Autodesk Fusion 360 part; units mm, degrees
(part 5 of 8)
sketch "Adapter Washer 4 Outer" plane through (-21.2132, -21.2132, 0) normal (0.707107, 0.707107, 0) x (0, 0, 1) in component "REF M4 Adapter Fasteners"
  circle A0 centre (22.6274, -22.6274) radius 4.5
  circle A1 centre (22.6274, -22.6274) radius 2.15
  dimension "d1308" = 22.6274
  dimension "d1309" = 22.6274
  dimension "d1310" = 9
  dimension "d1311" = 4.3
  measures "d1308" horizontal distance of origin A0.centre
  measures "d1309" vertical distance of origin A0.centre
  measures "d1310" diameter of A0
  measures "d1311" diameter of A1
extrude "Adapter Washer 4" add sketch "Adapter Washer 4 Outer" along normal blind 1 separate body makes body 52 in component "REF M4 Adapter Fasteners"
ref_plane "WorkPlane16" through (-3.182, -3.182, 12.125) normal (0.707107, 0.707107, 0) x (0, 0, 1) in component "REF M4 Adapter Fasteners"
sketch "Adapter Nut Hex 4" plane through (-3.182, -3.182, 0) normal (0.707107, 0.707107, 0) x (0, 0, 1) in component "REF M4 Adapter Fasteners"
  circle A0 centre (22.6274, -22.6274) radius 4.0415 construction
  line L0 (26.6689, -22.6274) -> (24.6481, -19.1274)
  line L1 (24.6481, -19.1274) -> (20.6067, -19.1274)
  line L2 (20.6067, -19.1274) -> (18.586, -22.6274)
  line L3 (18.586, -22.6274) -> (20.6067, -26.1274)
  line L4 (20.6067, -26.1274) -> (24.6481, -26.1274)
  line L5 (24.6481, -26.1274) -> (26.6689, -22.6274)
  dimension "d1316" = 22.6274
  dimension "d1317" = 22.6274
  dimension "d1318" = 8.0829
  constraint coincident A0 L0.start
  constraint coincident A0 L0.end
  constraint coincident A0 L1.end
  constraint coincident A0 L2.end
  constraint coincident A0 L3.end
  constraint coincident A0 L4.end
  constraint equal L0 L1
  constraint equal L0 L2
  constraint equal L0 L3
  constraint equal L0 L4
  constraint equal L0 L5
  constraint horizontal L1
  measures "d1316" horizontal distance of origin A0.centre
  measures "d1317" vertical distance of origin A0.centre
  measures "d1318" diameter of A0
extrude "Adapter Nut 4" add sketch "Adapter Nut Hex 4" along normal blind 3.2 separate body makes body 53 in component "REF M4 Adapter Fasteners"
sketch "Nut Thread Clearance 4" plane through (-3.182, -3.182, 0) normal (0.707107, 0.707107, 0) x (0, 0, 1) in component "REF M4 Adapter Fasteners"
  circle A0 centre (22.6274, -22.6274) radius 2.15
  dimension "d1321" = 22.6274
  dimension "d1322" = 22.6274
  dimension "d1323" = 4.3
  measures "d1321" horizontal distance of origin A0.centre
  measures "d1322" vertical distance of origin A0.centre
  measures "d1323" diameter of A0
extrude "Nut Bore 4" cut sketch "Nut Thread Clearance 4" along normal blind 3.2 bodies 53 in component "REF M4 Adapter Fasteners"
ref_plane "WorkPlane1" through (0, 0, 12.125) normal (0.707107, 0.707107, 0) x (0, 0, 1) in component "REF M3 Support Fasteners"
sketch "M3 Pattern Axis" plane through (0, 0, 0) normal (0.707107, 0.707107, 0) x (0, 0, 1) in component "REF M3 Support Fasteners"
  circle A0 centre (0, 0) radius 0.5
  dimension "d1328" = 1
  measures "d1328" diameter of A0
ref_plane "WorkPlane2" through (-6.1518, -6.1518, 12.125) normal (0.707107, 0.707107, 0) x (0, 0, 1) in component "REF M3 Support Fasteners"
sketch "M3 Shank Profile" plane through (-6.1518, -6.1518, 0) normal (0.707107, 0.707107, 0) x (0, 0, 1) in component "REF M3 Support Fasteners"
  line L0 (0, 0) -> (17, 0) construction
  circle A0 centre (17, 0) radius 1.5
  dimension "d1331" = 17
  dimension "d1332" = 3
  constraint horizontal L0
  measures "d1331" distance of L0.start L0.end
  measures "d1332" diameter of A0
extrude "M3 Shank" add sketch "M3 Shank Profile" along normal blind 45 separate body makes body 54 in component "REF M3 Support Fasteners"
ref_plane "WorkPlane3" through (25.668, 25.668, 12.125) normal (0.707107, 0.707107, 0) x (0, 0, 1) in component "REF M3 Support Fasteners"
sketch "M3 Head Profile" plane through (25.668, 25.668, 0) normal (0.707107, 0.707107, 0) x (0, 0, 1) in component "REF M3 Support Fasteners"
  line L0 (0, 0) -> (17, 0) construction
  circle A0 centre (17, 0) radius 2.75
  dimension "d1337" = 17
  dimension "d1338" = 5.5
  constraint horizontal L0
  measures "d1337" distance of L0.start L0.end
  measures "d1338" diameter of A0
extrude "M3 Head" add sketch "M3 Head Profile" along normal blind 3 separate body makes body 55 in component "REF M3 Support Fasteners"
ref_plane "WorkPlane4" through (25.3144, 25.3144, 12.125) normal (0.707107, 0.707107, 0) x (0, 0, 1) in component "REF M3 Support Fasteners"
sketch "Rear M3 Washer Profile" plane through (25.3144, 25.3144, 0) normal (0.707107, 0.707107, 0) x (0, 0, 1) in component "REF M3 Support Fasteners"
  line L0 (0, 0) -> (17, 0) construction
  circle A0 centre (17, 0) radius 3.5
  circle A1 centre (17, 0) radius 1.65
  dimension "d1343" = 17
  dimension "d1344" = 7
  dimension "d1345" = 3.3
  constraint horizontal L0
  measures "d1343" distance of L0.start L0.end
  measures "d1344" diameter of A0
  measures "d1345" diameter of A1
extrude "Rear M3 Washer" add sketch "Rear M3 Washer Profile" along normal blind 0.5 separate body makes body 56 in component "REF M3 Support Fasteners"
ref_plane "WorkPlane5" through (-2.1213, -2.1213, 12.125) normal (0.707107, 0.707107, 0) x (0, 0, 1) in component "REF M3 Support Fasteners"
sketch "Front M3 Washer Profile" plane through (-2.1213, -2.1213, 0) normal (0.707107, 0.707107, 0) x (0, 0, 1) in component "REF M3 Support Fasteners"
  line L0 (0, 0) -> (17, 0) construction
  circle A0 centre (17, 0) radius 3.5
  circle A1 centre (17, 0) radius 1.65
  dimension "d1350" = 17
  dimension "d1351" = 7
  dimension "d1352" = 3.3
  constraint horizontal L0
  measures "d1350" distance of L0.start L0.end
  measures "d1351" diameter of A0
  measures "d1352" diameter of A1
extrude "Front M3 Washer" add sketch "Front M3 Washer Profile" along normal blind 0.5 separate body makes body 57 in component "REF M3 Support Fasteners"
ref_plane "WorkPlane6" through (-4.9497, -4.9497, 12.125) normal (0.707107, 0.707107, 0) x (0, 0, 1) in component "REF M3 Support Fasteners"
sketch "Front M3 Nyloc Envelope Profile" plane through (-4.9497, -4.9497, 0) normal (0.707107, 0.707107, 0) x (0, 0, 1) in component "REF M3 Support Fasteners"
  line L0 (0, 0) -> (17, 0) construction
  circle A0 centre (17, 0) radius 3.18
  circle A1 centre (17, 0) radius 1.65
  dimension "d1357" = 17
  dimension "d1358" = 6.36
  dimension "d1359" = 3.3
  constraint horizontal L0
  measures "d1357" distance of L0.start L0.end
  measures "d1358" diameter of A0
  measures "d1359" diameter of A1
extrude "Front M3 Nyloc Envelope" add sketch "Front M3 Nyloc Envelope Profile" along normal blind 4 separate body makes body 58 in component "REF M3 Support Fasteners"
pattern_circular "Three M3 Support Sets" count 3 over 360 about axis through (0, 0, 0) along (0.707107, 0.707107, 0) of "M3 Shank", "M3 Head", "Rear M3 Washer", "Front M3 Washer", "Front M3 Nyloc Envelope" makes body 59 at (26.4156, 3.7072, -9.1843) makes body 60 at (38.5579, 14.1923, -9.631) makes body 61 at (37.5691, 13.0597, -9.7105) makes body 62 at (10.487, -14.0225, -9.7105) makes body 63 at (8.453, -16.4669, -9.8079) makes body 64 at (5.063, 25.0597, -7.1178) makes body 65 at (15.0384, 39.126, -9.992) makes body 66 at (13.2406, 37.3882, -10.1537) makes body 67 at (-13.8416, 10.306, -10.1537) makes body 68 at (-16.243, 8.2291, -10.3563) in component "REF M3 Support Fasteners"
component "A Housing" placed x (1, 0, 0) y (0, 1, 0) z (0, 0, 1) at (0, 0, 0)
component "B Moving Body" placed x (1, 0, 0) y (0, 1, 0) z (0, 0, 1) at (0, 0, 0)
component "D Rear Bearing Holder" placed x (1, 0, 0) y (0, 1, 0) z (0, 0, 1) at (0, 0, 0)
component "C Front Bearing Cap" placed x (1, 0, 0) y (0, 1, 0) z (0, 0, 1) at (0, 0, 0)
component "E Rear Bearing Cap" placed x (1, 0, 0) y (0, 1, 0) z (0, 0, 1) at (0, 0, 0)
component "F Metal Hub Adapter" placed x (1, 0, 0) y (0, 1, 0) z (0, 0, 1) at (0, 0, 0)
component "REF Two 608 Bearings" placed x (1, 0, 0) y (0, 1, 0) z (0, 0, 1) at (0, 0, 0)
component "REF Steel Shaft 8 x 60" placed x (1, 0, 0) y (0, 1, 0) z (0, 0, 1) at (0, 0, 0)
component "REF Inner Ring Spacers" placed x (1, 0, 0) y (0, 1, 0) z (0, 0, 1) at (0, 0, 0)
component "REF Split Collar Envelopes" placed x (1, 0, 0) y (0, 1, 0) z (0, 0, 1) at (0, 0, 0)
component "REF Metal Support Spacers" placed x (1, 0, 0) y (0, 1, 0) z (0, 0, 1) at (0, 0, 0)
component "REF Hub Compression Sleeves" placed x (1, 0, 0) y (0, 1, 0) z (0, 0, 1) at (0, 0, 0)
component "REF Sonic Hub Envelope" placed x (1, 0, 0) y (0, 1, 0) z (0, 0, 1) at (0, 0, 0)
component "REF M4 Hub Screws" placed x (1, 0, 0) y (0, 1, 0) z (0, 0, 1) at (0, 0, 0)
component "REF M4 Adapter Fasteners" placed x (1, 0, 0) y (0, 1, 0) z (0, 0, 1) at (0, 0, 0)
component "REF M3 Support Fasteners" placed x (1, 0, 0) y (0, 1, 0) z (0, 0, 1) at (0, 0, 0)
equation "bodyWidth = 150 mm" comment "Regular octagon across flats; corner diameter is larger."
equation "bodyLength = 260 mm" comment "Overall straight length of the shared master blank."
equation "splitAngle = 45 deg" comment "Keep this lesson angle at45 degrees."
equation "faceGap = 1 mm" comment "Gap between the two printed joint faces."
equation "wall = 4.5 mm" comment "Integrated shell and side brace radial thickness."
equation "faceHalfWidth = bodyWidth * ( sqrt(2) - 1 ) / 2" comment "Half-width of each outer planar facet."
equation "memberWidth = 8 mm" comment "Nominal brace and corner chord width in a facet."
equation "nodeHalfWidth = faceHalfWidth - memberWidth / 2" comment "Chord centerlines measured from facet center."
equation "jointNodeQ = 7 mm" comment "First truss skeleton row from the center joint plane."
equation "endRim = 10 mm" comment "Uncut axial rim at each distant end."
equation "endNodeX = bodyLength / 2 - endRim + memberWidth / 2" comment "Last skeleton row before aperture inset."
equation "apertureRadius = 1.5 mm" comment "Rounded internal corners at triangular openings."
equation "spokeWidth = 10 mm" comment "Width of each deep bearing bulkhead spoke."
equation "spokeDepth = 18 mm" comment "Bulkhead depth normal to the diagonal joint face."
equation "carrierOD = 52 mm" comment "Outside of integrated A front bearing carrier."
equation "rearCarrierClearance = 46 mm" comment "Internal carrier relief above front bearing shoulder."
equation "tubeCornerChamfer = 0.5 mm" comment "Exposed outside octagon corner bevel."
equation "tubeRimChamfer = 0.3 mm" comment "End rim and print-contact edge relief."
equation "cordStation = bodyLength / 2 - endRim / 2" comment "Load-test cord port center measured along body X."
equation "bearingOD = 22 mm" comment "608 measured outside diameter."
equation "bearingID = 8 mm" comment "608 bore."
equation "bearingWidth = 7 mm" comment "608 width."
equation "seatAllowance = 0.2 mm" comment "Trial DIAMETRAL clearance; choose with printed coupon."
equation "seatDiameter = bearingOD + seatAllowance" comment "Measured fit controls this."
equation "coreOD = 44 mm" comment "Bearing holder outer diameter."
equation "raceRelief = 19.5 mm" comment "Outer-ring shoulder opening; verify seals."
equation "frontSeatDepth = 7.1 mm" comment "0.1 mm outer-ring axial allowance."
equation "rearSeatDepth = 7.2 mm" comment "0.2 mm outer-ring axial float."
equation "shoulder = 3 mm" comment "Backing behind each bearing seat."
equation "supportSpacer = 12 mm" comment "Purchased metal M3 spacer length."
equation "supportCircle = 34 mm" comment "Three M3 support bolts."
equation "supportSpacerOD = 6 mm" comment "Purchased spacer outside diameter."
equation "capThickness = 3 mm" comment "Both printed outer-ring retaining caps."
equation "m3Clearance = 3.3 mm" comment "M3 through holes."
equation "m4Clearance = 4.3 mm" comment "M4 through holes."
equation "qFront = faceGap / 2" comment "Front bearing starts at A mating face."
equation "qFrontBack = qFront + frontSeatDepth + shoulder" comment "End of integrated A holder."
equation "qRearBase = qFrontBack + supportSpacer" comment "Start of removable rear holder."
equation "qRearBearing = qRearBase + shoulder" comment "Rear bearing inner end."
equation "qRearEnd = qRearBearing + rearSeatDepth" comment "Rear holder outer end."
equation "bearingSpacing = qRearBearing - qFront" comment "Derived support-center spacing, not a bearing rating."
equation "mountOD = 76 mm" comment "B mount and F flange outside diameter."
equation "mountCircle = 64 mm" comment "Four M4 attachment holes."
equation "mountOpening = 50.3 mm" comment "B through opening."
equation "hubFace = -23 mm" comment "Metal hub flat mounting face."
equation "adapterThickness = 6 mm" comment "F flange and metal compression sleeve length."
equation "pilotDiameter = 50 mm" comment "F shallow centering pilot."
equation "pilotInside = 34 mm" comment "Clearance around metal hub."
equation "pilotHeight = 2 mm" comment "Short pilot only."
equation "hubHoleSpacing = 16 mm" comment "Metal Sonic hub square hole spacing."
equation "sleeveOD = 8 mm" comment "M4 metal compression sleeves."
equation "sleeveAllowance = 0.2 mm" comment "Trial DIAMETRAL sleeve clearance."
equation "shaftClearance = 8.5 mm" comment "F clearance hole; not a bearing."
equation "nutAF = 7.2 mm" comment "M4 nominal 7 AF nut trial pocket."
equation "nutDepth = 4 mm" comment "Open front M4 nut pocket."
equation "rootRadius = 1 mm" comment "Hub-to-wall blend."
equation "entryChamfer = 0.4 mm" comment "Assembly lead-in."
equation "bedRelief = 0.3 mm" comment "Bed-contact edge allowance."
equation "d59 = bodyWidth"
equation "d60 = bodyLength"
equation "d62 = splitAngle"
equation "d64 = -faceGap / 2"
equation "d65 = -faceGap / 2"
equation "d66 = wall"
equation "d67 = wall"
equation "d70 = bodyWidth / 2"
equation "d72 = abs(( 1 ) * ( ( ( 1 ) * jointNodeQ * sqrt(2) - bodyWidth / 2 * cos(0 deg) + ( ( -1 ) * nodeHalfWidth ) * sin(0 deg) ) + ( 0 ) * ( ( 1 ) * endNodeX - ( ( 1 ) * jointNodeQ * sqrt(2) - bodyWidth / 2 * cos(0 deg) + ( ( -1 ) * nodeHalfWidth ) * sin(0 deg) ) ) ) + ( 0 ) * ( ( -1 ) * nodeHalfWidth ))"
equation "d73 = abs(( 0 ) * ( ( ( 1 ) * jointNodeQ * sqrt(2) - bodyWidth / 2 * cos(0 deg) + ( ( -1 ) * nodeHalfWidth ) * sin(0 deg) ) + ( 0 ) * ( ( 1 ) * endNodeX - ( ( 1 ) * jointNodeQ * sqrt(2) - bodyWidth / 2 * cos(0 deg) + ( ( -1 ) * nodeHalfWidth ) * sin(0 deg) ) ) ) + ( -1 ) * ( ( -1 ) * nodeHalfWidth ))"
equation "d74 = abs(( 1 ) * ( ( ( 1 ) * jointNodeQ * sqrt(2) - bodyWidth / 2 * cos(0 deg) + ( ( 1 ) * nodeHalfWidth ) * sin(0 deg) ) + ( 0 ) * ( ( 1 ) * endNodeX - ( ( 1 ) * jointNodeQ * sqrt(2) - bodyWidth / 2 * cos(0 deg) + ( ( 1 ) * nodeHalfWidth ) * sin(0 deg) ) ) ) + ( 0 ) * ( ( 1 ) * nodeHalfWidth ))"
equation "d75 = abs(( 0 ) * ( ( ( 1 ) * jointNodeQ * sqrt(2) - bodyWidth / 2 * cos(0 deg) + ( ( 1 ) * nodeHalfWidth ) * sin(0 deg) ) + ( 0 ) * ( ( 1 ) * endNodeX - ( ( 1 ) * jointNodeQ * sqrt(2) - bodyWidth / 2 * cos(0 deg) + ( ( 1 ) * nodeHalfWidth ) * sin(0 deg) ) ) ) + ( -1 ) * ( ( 1 ) * nodeHalfWidth ))"
equation "d76 = abs(( 1 ) * ( ( ( 1 ) * jointNodeQ * sqrt(2) - bodyWidth / 2 * cos(0 deg) + ( ( -1 ) * nodeHalfWidth ) * sin(0 deg) ) + ( 0.666666666666667 ) * ( ( 1 ) * endNodeX - ( ( 1 ) * jointNodeQ * sqrt(2) - bodyWidth / 2 * cos(0 deg) + ( ( -1 ) * nodeHalfWidth ) * sin(0 deg) ) ) ) + ( 0 ) * ( ( -1 ) * nodeHalfWidth ))"
equation "d77 = abs(( 0 ) * ( ( ( 1 ) * jointNodeQ * sqrt(2) - bodyWidth / 2 * cos(0 deg) + ( ( -1 ) * nodeHalfWidth ) * sin(0 deg) ) + ( 0.666666666666667 ) * ( ( 1 ) * endNodeX - ( ( 1 ) * jointNodeQ * sqrt(2) - bodyWidth / 2 * cos(0 deg) + ( ( -1 ) * nodeHalfWidth ) * sin(0 deg) ) ) ) + ( -1 ) * ( ( -1 ) * nodeHalfWidth ))"
equation "d78 = -memberWidth / 2"
equation "d79 = -( wall + 0.2 mm )"
equation "d81 = abs(( 1 ) * ( ( ( 1 ) * jointNodeQ * sqrt(2) - bodyWidth / 2 * cos(0 deg) + ( ( 1 ) * nodeHalfWidth ) * sin(0 deg) ) + ( 0 ) * ( ( 1 ) * endNodeX - ( ( 1 ) * jointNodeQ * sqrt(2) - bodyWidth / 2 * cos(0 deg) + ( ( 1 ) * nodeHalfWidth ) * sin(0 deg) ) ) ) + ( 0 ) * ( ( 1 ) * nodeHalfWidth ))"
equation "d82 = abs(( 0 ) * ( ( ( 1 ) * jointNodeQ * sqrt(2) - bodyWidth / 2 * cos(0 deg) + ( ( 1 ) * nodeHalfWidth ) * sin(0 deg) ) + ( 0 ) * ( ( 1 ) * endNodeX - ( ( 1 ) * jointNodeQ * sqrt(2) - bodyWidth / 2 * cos(0 deg) + ( ( 1 ) * nodeHalfWidth ) * sin(0 deg) ) ) ) + ( -1 ) * ( ( 1 ) * nodeHalfWidth ))"
equation "d83 = abs(( 1 ) * ( ( ( 1 ) * jointNodeQ * sqrt(2) - bodyWidth / 2 * cos(0 deg) + ( ( -1 ) * nodeHalfWidth ) * sin(0 deg) ) + ( 0.666666666666667 ) * ( ( 1 ) * endNodeX - ( ( 1 ) * jointNodeQ * sqrt(2) - bodyWidth / 2 * cos(0 deg) + ( ( -1 ) * nodeHalfWidth ) * sin(0 deg) ) ) ) + ( 0 ) * ( ( -1 ) * nodeHalfWidth ))"
equation "d84 = abs(( 0 ) * ( ( ( 1 ) * jointNodeQ * sqrt(2) - bodyWidth / 2 * cos(0 deg) + ( ( -1 ) * nodeHalfWidth ) * sin(0 deg) ) + ( 0.666666666666667 ) * ( ( 1 ) * endNodeX - ( ( 1 ) * jointNodeQ * sqrt(2) - bodyWidth / 2 * cos(0 deg) + ( ( -1 ) * nodeHalfWidth ) * sin(0 deg) ) ) ) + ( -1 ) * ( ( -1 ) * nodeHalfWidth ))"
equation "d85 = abs(( 1 ) * ( ( ( 1 ) * jointNodeQ * sqrt(2) - bodyWidth / 2 * cos(0 deg) + ( ( 1 ) * nodeHalfWidth ) * sin(0 deg) ) + ( 0.833333333333333 ) * ( ( 1 ) * endNodeX - ( ( 1 ) * jointNodeQ * sqrt(2) - bodyWidth / 2 * cos(0 deg) + ( ( 1 ) * nodeHalfWidth ) * sin(0 deg) ) ) ) + ( 0 ) * ( ( 1 ) * nodeHalfWidth ))"
equation "d86 = abs(( 0 ) * ( ( ( 1 ) * jointNodeQ * sqrt(2) - bodyWidth / 2 * cos(0 deg) + ( ( 1 ) * nodeHalfWidth ) * sin(0 deg) ) + ( 0.833333333333333 ) * ( ( 1 ) * endNodeX - ( ( 1 ) * jointNodeQ * sqrt(2) - bodyWidth / 2 * cos(0 deg) + ( ( 1 ) * nodeHalfWidth ) * sin(0 deg) ) ) ) + ( -1 ) * ( ( 1 ) * nodeHalfWidth ))"
equation "d87 = memberWidth / 2"
equation "d88 = -( wall + 0.2 mm )"
equation "d90 = abs(( 1 ) * ( ( ( 1 ) * jointNodeQ * sqrt(2) - bodyWidth / 2 * cos(0 deg) + ( ( -1 ) * nodeHalfWidth ) * sin(0 deg) ) + ( 0.666666666666667 ) * ( ( 1 ) * endNodeX - ( ( 1 ) * jointNodeQ * sqrt(2) - bodyWidth / 2 * cos(0 deg) + ( ( -1 ) * nodeHalfWidth ) * sin(0 deg) ) ) ) + ( 0 ) * ( ( -1 ) * nodeHalfWidth ))"
equation "d91 = abs(( 0 ) * ( ( ( 1 ) * jointNodeQ * sqrt(2) - bodyWidth / 2 * cos(0 deg) + ( ( -1 ) * nodeHalfWidth ) * sin(0 deg) ) + ( 0.666666666666667 ) * ( ( 1 ) * endNodeX - ( ( 1 ) * jointNodeQ * sqrt(2) - bodyWidth / 2 * cos(0 deg) + ( ( -1 ) * nodeHalfWidth ) * sin(0 deg) ) ) ) + ( -1 ) * ( ( -1 ) * nodeHalfWidth ))"
equation "d92 = abs(( 1 ) * ( ( ( 1 ) * jointNodeQ * sqrt(2) - bodyWidth / 2 * cos(0 deg) + ( ( 1 ) * nodeHalfWidth ) * sin(0 deg) ) + ( 0.833333333333333 ) * ( ( 1 ) * endNodeX - ( ( 1 ) * jointNodeQ * sqrt(2) - bodyWidth / 2 * cos(0 deg) + ( ( 1 ) * nodeHalfWidth ) * sin(0 deg) ) ) ) + ( 0 ) * ( ( 1 ) * nodeHalfWidth ))"
equation "d93 = abs(( 0 ) * ( ( ( 1 ) * jointNodeQ * sqrt(2) - bodyWidth / 2 * cos(0 deg) + ( ( 1 ) * nodeHalfWidth ) * sin(0 deg) ) + ( 0.833333333333333 ) * ( ( 1 ) * endNodeX - ( ( 1 ) * jointNodeQ * sqrt(2) - bodyWidth / 2 * cos(0 deg) + ( ( 1 ) * nodeHalfWidth ) * sin(0 deg) ) ) ) + ( -1 ) * ( ( 1 ) * nodeHalfWidth ))"
equation "d94 = abs(( 1 ) * ( ( ( 1 ) * jointNodeQ * sqrt(2) - bodyWidth / 2 * cos(0 deg) + ( ( -1 ) * nodeHalfWidth ) * sin(0 deg) ) + ( 1 ) * ( ( 1 ) * endNodeX - ( ( 1 ) * jointNodeQ * sqrt(2) - bodyWidth / 2 * cos(0 deg) + ( ( -1 ) * nodeHalfWidth ) * sin(0 deg) ) ) ) + ( 0 ) * ( ( -1 ) * nodeHalfWidth ))"
equation "d95 = abs(( 0 ) * ( ( ( 1 ) * jointNodeQ * sqrt(2) - bodyWidth / 2 * cos(0 deg) + ( ( -1 ) * nodeHalfWidth ) * sin(0 deg) ) + ( 1 ) * ( ( 1 ) * endNodeX - ( ( 1 ) * jointNodeQ * sqrt(2) - bodyWidth / 2 * cos(0 deg) + ( ( -1 ) * nodeHalfWidth ) * sin(0 deg) ) ) ) + ( -1 ) * ( ( -1 ) * nodeHalfWidth ))"
equation "d96 = -memberWidth / 2"
equation "d97 = -( wall + 0.2 mm )"
equation "d99 = abs(( 1 ) * ( ( ( 1 ) * jointNodeQ * sqrt(2) - bodyWidth / 2 * cos(0 deg) + ( ( 1 ) * nodeHalfWidth ) * sin(0 deg) ) + ( 0.833333333333333 ) * ( ( 1 ) * endNodeX - ( ( 1 ) * jointNodeQ * sqrt(2) - bodyWidth / 2 * cos(0 deg) + ( ( 1 ) * nodeHalfWidth ) * sin(0 deg) ) ) ) + ( 0 ) * ( ( 1 ) * nodeHalfWidth ))"
equation "d100 = abs(( 0 ) * ( ( ( 1 ) * jointNodeQ * sqrt(2) - bodyWidth / 2 * cos(0 deg) + ( ( 1 ) * nodeHalfWidth ) * sin(0 deg) ) + ( 0.833333333333333 ) * ( ( 1 ) * endNodeX - ( ( 1 ) * jointNodeQ * sqrt(2) - bodyWidth / 2 * cos(0 deg) + ( ( 1 ) * nodeHalfWidth ) * sin(0 deg) ) ) ) + ( -1 ) * ( ( 1 ) * nodeHalfWidth ))"
equation "d101 = abs(( 1 ) * ( ( ( 1 ) * jointNodeQ * sqrt(2) - bodyWidth / 2 * cos(0 deg) + ( ( -1 ) * nodeHalfWidth ) * sin(0 deg) ) + ( 1 ) * ( ( 1 ) * endNodeX - ( ( 1 ) * jointNodeQ * sqrt(2) - bodyWidth / 2 * cos(0 deg) + ( ( -1 ) * nodeHalfWidth ) * sin(0 deg) ) ) ) + ( 0 ) * ( ( -1 ) * nodeHalfWidth ))"
equation "d102 = abs(( 0 ) * ( ( ( 1 ) * jointNodeQ * sqrt(2) - bodyWidth / 2 * cos(0 deg) + ( ( -1 ) * nodeHalfWidth ) * sin(0 deg) ) + ( 1 ) * ( ( 1 ) * endNodeX - ( ( 1 ) * jointNodeQ * sqrt(2) - bodyWidth / 2 * cos(0 deg) + ( ( -1 ) * nodeHalfWidth ) * sin(0 deg) ) ) ) + ( -1 ) * ( ( -1 ) * nodeHalfWidth ))"
equation "d103 = abs(( 1 ) * ( ( ( 1 ) * jointNodeQ * sqrt(2) - bodyWidth / 2 * cos(0 deg) + ( ( 1 ) * nodeHalfWidth ) * sin(0 deg) ) + ( 1 ) * ( ( 1 ) * endNodeX - ( ( 1 ) * jointNodeQ * sqrt(2) - bodyWidth / 2 * cos(0 deg) + ( ( 1 ) * nodeHalfWidth ) * sin(0 deg) ) ) ) + ( 0 ) * ( ( 1 ) * nodeHalfWidth ))"
equation "d104 = abs(( 0 ) * ( ( ( 1 ) * jointNodeQ * sqrt(2) - bodyWidth / 2 * cos(0 deg) + ( ( 1 ) * nodeHalfWidth ) * sin(0 deg) ) + ( 1 ) * ( ( 1 ) * endNodeX - ( ( 1 ) * jointNodeQ * sqrt(2) - bodyWidth / 2 * cos(0 deg) + ( ( 1 ) * nodeHalfWidth ) * sin(0 deg) ) ) ) + ( -1 ) * ( ( 1 ) * nodeHalfWidth ))"
equation "d105 = memberWidth / 2"
equation "d106 = -( wall + 0.2 mm )"
equation "d109 = apertureRadius"
equation "d112 = bodyWidth / 2"
equation "d114 = abs(( 1 ) * ( ( ( 1 ) * jointNodeQ * sqrt(2) - bodyWidth / 2 * cos(45 deg) + ( ( -1 ) * nodeHalfWidth ) * sin(45 deg) ) + ( 0 ) * ( ( 1 ) * endNodeX - ( ( 1 ) * jointNodeQ * sqrt(2) - bodyWidth / 2 * cos(45 deg) + ( ( -1 ) * nodeHalfWidth ) * sin(45 deg) ) ) ) + ( 0 ) * ( ( -1 ) * nodeHalfWidth ))"
equation "d115 = abs(( 0 ) * ( ( ( 1 ) * jointNodeQ * sqrt(2) - bodyWidth / 2 * cos(45 deg) + ( ( -1 ) * nodeHalfWidth ) * sin(45 deg) ) + ( 0 ) * ( ( 1 ) * endNodeX - ( ( 1 ) * jointNodeQ * sqrt(2) - bodyWidth / 2 * cos(45 deg) + ( ( -1 ) * nodeHalfWidth ) * sin(45 deg) ) ) ) + ( -1 ) * ( ( -1 ) * nodeHalfWidth ))"
equation "d116 = abs(( 1 ) * ( ( ( 1 ) * jointNodeQ * sqrt(2) - bodyWidth / 2 * cos(45 deg) + ( ( 1 ) * nodeHalfWidth ) * sin(45 deg) ) + ( 0 ) * ( ( 1 ) * endNodeX - ( ( 1 ) * jointNodeQ * sqrt(2) - bodyWidth / 2 * cos(45 deg) + ( ( 1 ) * nodeHalfWidth ) * sin(45 deg) ) ) ) + ( 0 ) * ( ( 1 ) * nodeHalfWidth ))"
equation "d117 = abs(( 0 ) * ( ( ( 1 ) * jointNodeQ * sqrt(2) - bodyWidth / 2 * cos(45 deg) + ( ( 1 ) * nodeHalfWidth ) * sin(45 deg) ) + ( 0 ) * ( ( 1 ) * endNodeX - ( ( 1 ) * jointNodeQ * sqrt(2) - bodyWidth / 2 * cos(45 deg) + ( ( 1 ) * nodeHalfWidth ) * sin(45 deg) ) ) ) + ( -1 ) * ( ( 1 ) * nodeHalfWidth ))"
equation "d118 = abs(( 1 ) * ( ( ( 1 ) * jointNodeQ * sqrt(2) - bodyWidth / 2 * cos(45 deg) + ( ( -1 ) * nodeHalfWidth ) * sin(45 deg) ) + ( 0.333333333333333 ) * ( ( 1 ) * endNodeX - ( ( 1 ) * jointNodeQ * sqrt(2) - bodyWidth / 2 * cos(45 deg) + ( ( -1 ) * nodeHalfWidth ) * sin(45 deg) ) ) ) + ( 0 ) * ( ( -1 ) * nodeHalfWidth ))"
equation "d119 = abs(( 0 ) * ( ( ( 1 ) * jointNodeQ * sqrt(2) - bodyWidth / 2 * cos(45 deg) + ( ( -1 ) * nodeHalfWidth ) * sin(45 deg) ) + ( 0.333333333333333 ) * ( ( 1 ) * endNodeX - ( ( 1 ) * jointNodeQ * sqrt(2) - bodyWidth / 2 * cos(45 deg) + ( ( -1 ) * nodeHalfWidth ) * sin(45 deg) ) ) ) + ( -1 ) * ( ( -1 ) * nodeHalfWidth ))"
equation "d120 = -memberWidth / 2"
equation "d121 = -( wall + 0.2 mm )"
equation "d123 = abs(( 1 ) * ( ( ( 1 ) * jointNodeQ * sqrt(2) - bodyWidth / 2 * cos(45 deg) + ( ( 1 ) * nodeHalfWidth ) * sin(45 deg) ) + ( 0 ) * ( ( 1 ) * endNodeX - ( ( 1 ) * jointNodeQ * sqrt(2) - bodyWidth / 2 * cos(45 deg) + ( ( 1 ) * nodeHalfWidth ) * sin(45 deg) ) ) ) + ( 0 ) * ( ( 1 ) * nodeHalfWidth ))"
equation "d124 = abs(( 0 ) * ( ( ( 1 ) * jointNodeQ * sqrt(2) - bodyWidth / 2 * cos(45 deg) + ( ( 1 ) * nodeHalfWidth ) * sin(45 deg) ) + ( 0 ) * ( ( 1 ) * endNodeX - ( ( 1 ) * jointNodeQ * sqrt(2) - bodyWidth / 2 * cos(45 deg) + ( ( 1 ) * nodeHalfWidth ) * sin(45 deg) ) ) ) + ( -1 ) * ( ( 1 ) * nodeHalfWidth ))"
equation "d125 = abs(( 1 ) * ( ( ( 1 ) * jointNodeQ * sqrt(2) - bodyWidth / 2 * cos(45 deg) + ( ( -1 ) * nodeHalfWidth ) * sin(45 deg) ) + ( 0.333333333333333 ) * ( ( 1 ) * endNodeX - ( ( 1 ) * jointNodeQ * sqrt(2) - bodyWidth / 2 * cos(45 deg) + ( ( -1 ) * nodeHalfWidth ) * sin(45 deg) ) ) ) + ( 0 ) * ( ( -1 ) * nodeHalfWidth ))"
equation "d126 = abs(( 0 ) * ( ( ( 1 ) * jointNodeQ * sqrt(2) - bodyWidth / 2 * cos(45 deg) + ( ( -1 ) * nodeHalfWidth ) * sin(45 deg) ) + ( 0.333333333333333 ) * ( ( 1 ) * endNodeX - ( ( 1 ) * jointNodeQ * sqrt(2) - bodyWidth / 2 * cos(45 deg) + ( ( -1 ) * nodeHalfWidth ) * sin(45 deg) ) ) ) + ( -1 ) * ( ( -1 ) * nodeHalfWidth ))"
equation "d127 = abs(( 1 ) * ( ( ( 1 ) * jointNodeQ * sqrt(2) - bodyWidth / 2 * cos(45 deg) + ( ( 1 ) * nodeHalfWidth ) * sin(45 deg) ) + ( 0.666666666666667 ) * ( ( 1 ) * endNodeX - ( ( 1 ) * jointNodeQ * sqrt(2) - bodyWidth / 2 * cos(45 deg) + ( ( 1 ) * nodeHalfWidth ) * sin(45 deg) ) ) ) + ( 0 ) * ( ( 1 ) * nodeHalfWidth ))"
equation "d128 = abs(( 0 ) * ( ( ( 1 ) * jointNodeQ * sqrt(2) - bodyWidth / 2 * cos(45 deg) + ( ( 1 ) * nodeHalfWidth ) * sin(45 deg) ) + ( 0.666666666666667 ) * ( ( 1 ) * endNodeX - ( ( 1 ) * jointNodeQ * sqrt(2) - bodyWidth / 2 * cos(45 deg) + ( ( 1 ) * nodeHalfWidth ) * sin(45 deg) ) ) ) + ( -1 ) * ( ( 1 ) * nodeHalfWidth ))"
equation "d129 = memberWidth / 2"
equation "d130 = -( wall + 0.2 mm )"
equation "d132 = abs(( 1 ) * ( ( ( 1 ) * jointNodeQ * sqrt(2) - bodyWidth / 2 * cos(45 deg) + ( ( -1 ) * nodeHalfWidth ) * sin(45 deg) ) + ( 0.333333333333333 ) * ( ( 1 ) * endNodeX - ( ( 1 ) * jointNodeQ * sqrt(2) - bodyWidth / 2 * cos(45 deg) + ( ( -1 ) * nodeHalfWidth ) * sin(45 deg) ) ) ) + ( 0 ) * ( ( -1 ) * nodeHalfWidth ))"
equation "d133 = abs(( 0 ) * ( ( ( 1 ) * jointNodeQ * sqrt(2) - bodyWidth / 2 * cos(45 deg) + ( ( -1 ) * nodeHalfWidth ) * sin(45 deg) ) + ( 0.333333333333333 ) * ( ( 1 ) * endNodeX - ( ( 1 ) * jointNodeQ * sqrt(2) - bodyWidth / 2 * cos(45 deg) + ( ( -1 ) * nodeHalfWidth ) * sin(45 deg) ) ) ) + ( -1 ) * ( ( -1 ) * nodeHalfWidth ))"
equation "d134 = abs(( 1 ) * ( ( ( 1 ) * jointNodeQ * sqrt(2) - bodyWidth / 2 * cos(45 deg) + ( ( 1 ) * nodeHalfWidth ) * sin(45 deg) ) + ( 0.666666666666667 ) * ( ( 1 ) * endNodeX - ( ( 1 ) * jointNodeQ * sqrt(2) - bodyWidth / 2 * cos(45 deg) + ( ( 1 ) * nodeHalfWidth ) * sin(45 deg) ) ) ) + ( 0 ) * ( ( 1 ) * nodeHalfWidth ))"
equation "d135 = abs(( 0 ) * ( ( ( 1 ) * jointNodeQ * sqrt(2) - bodyWidth / 2 * cos(45 deg) + ( ( 1 ) * nodeHalfWidth ) * sin(45 deg) ) + ( 0.666666666666667 ) * ( ( 1 ) * endNodeX - ( ( 1 ) * jointNodeQ * sqrt(2) - bodyWidth / 2 * cos(45 deg) + ( ( 1 ) * nodeHalfWidth ) * sin(45 deg) ) ) ) + ( -1 ) * ( ( 1 ) * nodeHalfWidth ))"
equation "d136 = abs(( 1 ) * ( ( ( 1 ) * jointNodeQ * sqrt(2) - bodyWidth / 2 * cos(45 deg) + ( ( -1 ) * nodeHalfWidth ) * sin(45 deg) ) + ( 1 ) * ( ( 1 ) * endNodeX - ( ( 1 ) * jointNodeQ * sqrt(2) - bodyWidth / 2 * cos(45 deg) + ( ( -1 ) * nodeHalfWidth ) * sin(45 deg) ) ) ) + ( 0 ) * ( ( -1 ) * nodeHalfWidth ))"
equation "d137 = abs(( 0 ) * ( ( ( 1 ) * jointNodeQ * sqrt(2) - bodyWidth / 2 * cos(45 deg) + ( ( -1 ) * nodeHalfWidth ) * sin(45 deg) ) + ( 1 ) * ( ( 1 ) * endNodeX - ( ( 1 ) * jointNodeQ * sqrt(2) - bodyWidth / 2 * cos(45 deg) + ( ( -1 ) * nodeHalfWidth ) * sin(45 deg) ) ) ) + ( -1 ) * ( ( -1 ) * nodeHalfWidth ))"
equation "d138 = -memberWidth / 2"
equation "d139 = -( wall + 0.2 mm )"
equation "d141 = abs(( 1 ) * ( ( ( 1 ) * jointNodeQ * sqrt(2) - bodyWidth / 2 * cos(45 deg) + ( ( 1 ) * nodeHalfWidth ) * sin(45 deg) ) + ( 0.666666666666667 ) * ( ( 1 ) * endNodeX - ( ( 1 ) * jointNodeQ * sqrt(2) - bodyWidth / 2 * cos(45 deg) + ( ( 1 ) * nodeHalfWidth ) * sin(45 deg) ) ) ) + ( 0 ) * ( ( 1 ) * nodeHalfWidth ))"
equation "d142 = abs(( 0 ) * ( ( ( 1 ) * jointNodeQ * sqrt(2) - bodyWidth / 2 * cos(45 deg) + ( ( 1 ) * nodeHalfWidth ) * sin(45 deg) ) + ( 0.666666666666667 ) * ( ( 1 ) * endNodeX - ( ( 1 ) * jointNodeQ * sqrt(2) - bodyWidth / 2 * cos(45 deg) + ( ( 1 ) * nodeHalfWidth ) * sin(45 deg) ) ) ) + ( -1 ) * ( ( 1 ) * nodeHalfWidth ))"
equation "d143 = abs(( 1 ) * ( ( ( 1 ) * jointNodeQ * sqrt(2) - bodyWidth / 2 * cos(45 deg) + ( ( -1 ) * nodeHalfWidth ) * sin(45 deg) ) + ( 1 ) * ( ( 1 ) * endNodeX - ( ( 1 ) * jointNodeQ * sqrt(2) - bodyWidth / 2 * cos(45 deg) + ( ( -1 ) * nodeHalfWidth ) * sin(45 deg) ) ) ) + ( 0 ) * ( ( -1 ) * nodeHalfWidth ))"
equation "d144 = abs(( 0 ) * ( ( ( 1 ) * jointNodeQ * sqrt(2) - bodyWidth / 2 * cos(45 deg) + ( ( -1 ) * nodeHalfWidth ) * sin(45 deg) ) + ( 1 ) * ( ( 1 ) * endNodeX - ( ( 1 ) * jointNodeQ * sqrt(2) - bodyWidth / 2 * cos(45 deg) + ( ( -1 ) * nodeHalfWidth ) * sin(45 deg) ) ) ) + ( -1 ) * ( ( -1 ) * nodeHalfWidth ))"
equation "d145 = abs(( 1 ) * ( ( ( 1 ) * jointNodeQ * sqrt(2) - bodyWidth / 2 * cos(45 deg) + ( ( 1 ) * nodeHalfWidth ) * sin(45 deg) ) + ( 1 ) * ( ( 1 ) * endNodeX - ( ( 1 ) * jointNodeQ * sqrt(2) - bodyWidth / 2 * cos(45 deg) + ( ( 1 ) * nodeHalfWidth ) * sin(45 deg) ) ) ) + ( 0 ) * ( ( 1 ) * nodeHalfWidth ))"
equation "d146 = abs(( 0 ) * ( ( ( 1 ) * jointNodeQ * sqrt(2) - bodyWidth / 2 * cos(45 deg) + ( ( 1 ) * nodeHalfWidth ) * sin(45 deg) ) + ( 1 ) * ( ( 1 ) * endNodeX - ( ( 1 ) * jointNodeQ * sqrt(2) - bodyWidth / 2 * cos(45 deg) + ( ( 1 ) * nodeHalfWidth ) * sin(45 deg) ) ) ) + ( -1 ) * ( ( 1 ) * nodeHalfWidth ))"
equation "d147 = memberWidth / 2"
equation "d148 = -( wall + 0.2 mm )"
equation "d151 = apertureRadius"
equation "d154 = bodyWidth / 2"
equation "d156 = abs(( 1 ) * ( ( ( 1 ) * jointNodeQ * sqrt(2) - bodyWidth / 2 * cos(90 deg) + ( ( -1 ) * nodeHalfWidth ) * sin(90 deg) ) + ( 0 ) * ( ( 1 ) * endNodeX - ( ( 1 ) * jointNodeQ * sqrt(2) - bodyWidth / 2 * cos(90 deg) + ( ( -1 ) * nodeHalfWidth ) * sin(90 deg) ) ) ) + ( 0 ) * ( ( -1 ) * nodeHalfWidth ))"
equation "d157 = abs(( 0 ) * ( ( ( 1 ) * jointNodeQ * sqrt(2) - bodyWidth / 2 * cos(90 deg) + ( ( -1 ) * nodeHalfWidth ) * sin(90 deg) ) + ( 0 ) * ( ( 1 ) * endNodeX - ( ( 1 ) * jointNodeQ * sqrt(2) - bodyWidth / 2 * cos(90 deg) + ( ( -1 ) * nodeHalfWidth ) * sin(90 deg) ) ) ) + ( -1 ) * ( ( -1 ) * nodeHalfWidth ))"
equation "d158 = abs(( 1 ) * ( ( ( 1 ) * jointNodeQ * sqrt(2) - bodyWidth / 2 * cos(90 deg) + ( ( 1 ) * nodeHalfWidth ) * sin(90 deg) ) + ( 0 ) * ( ( 1 ) * endNodeX - ( ( 1 ) * jointNodeQ * sqrt(2) - bodyWidth / 2 * cos(90 deg) + ( ( 1 ) * nodeHalfWidth ) * sin(90 deg) ) ) ) + ( 0 ) * ( ( 1 ) * nodeHalfWidth ))"
equation "d159 = abs(( 0 ) * ( ( ( 1 ) * jointNodeQ * sqrt(2) - bodyWidth / 2 * cos(90 deg) + ( ( 1 ) * nodeHalfWidth ) * sin(90 deg) ) + ( 0 ) * ( ( 1 ) * endNodeX - ( ( 1 ) * jointNodeQ * sqrt(2) - bodyWidth / 2 * cos(90 deg) + ( ( 1 ) * nodeHalfWidth ) * sin(90 deg) ) ) ) + ( -1 ) * ( ( 1 ) * nodeHalfWidth ))"
equation "d160 = abs(( 1 ) * ( ( ( 1 ) * jointNodeQ * sqrt(2) - bodyWidth / 2 * cos(90 deg) + ( ( -1 ) * nodeHalfWidth ) * sin(90 deg) ) + ( 0.5 ) * ( ( 1 ) * endNodeX - ( ( 1 ) * jointNodeQ * sqrt(2) - bodyWidth / 2 * cos(90 deg) + ( ( -1 ) * nodeHalfWidth ) * sin(90 deg) ) ) ) + ( 0 ) * ( ( -1 ) * nodeHalfWidth ))"
equation "d161 = abs(( 0 ) * ( ( ( 1 ) * jointNodeQ * sqrt(2) - bodyWidth / 2 * cos(90 deg) + ( ( -1 ) * nodeHalfWidth ) * sin(90 deg) ) + ( 0.5 ) * ( ( 1 ) * endNodeX - ( ( 1 ) * jointNodeQ * sqrt(2) - bodyWidth / 2 * cos(90 deg) + ( ( -1 ) * nodeHalfWidth ) * sin(90 deg) ) ) ) + ( -1 ) * ( ( -1 ) * nodeHalfWidth ))"
equation "d162 = -memberWidth / 2"
equation "d163 = -( wall + 0.2 mm )"
equation "d165 = abs(( 1 ) * ( ( ( 1 ) * jointNodeQ * sqrt(2) - bodyWidth / 2 * cos(90 deg) + ( ( 1 ) * nodeHalfWidth ) * sin(90 deg) ) + ( 0 ) * ( ( 1 ) * endNodeX - ( ( 1 ) * jointNodeQ * sqrt(2) - bodyWidth / 2 * cos(90 deg) + ( ( 1 ) * nodeHalfWidth ) * sin(90 deg) ) ) ) + ( 0 ) * ( ( 1 ) * nodeHalfWidth ))"
equation "d166 = abs(( 0 ) * ( ( ( 1 ) * jointNodeQ * sqrt(2) - bodyWidth / 2 * cos(90 deg) + ( ( 1 ) * nodeHalfWidth ) * sin(90 deg) ) + ( 0 ) * ( ( 1 ) * endNodeX - ( ( 1 ) * jointNodeQ * sqrt(2) - bodyWidth / 2 * cos(90 deg) + ( ( 1 ) * nodeHalfWidth ) * sin(90 deg) ) ) ) + ( -1 ) * ( ( 1 ) * nodeHalfWidth ))"
equation "d167 = abs(( 1 ) * ( ( ( 1 ) * jointNodeQ * sqrt(2) - bodyWidth / 2 * cos(90 deg) + ( ( -1 ) * nodeHalfWidth ) * sin(90 deg) ) + ( 0.5 ) * ( ( 1 ) * endNodeX - ( ( 1 ) * jointNodeQ * sqrt(2) - bodyWidth / 2 * cos(90 deg) + ( ( -1 ) * nodeHalfWidth ) * sin(90 deg) ) ) ) + ( 0 ) * ( ( -1 ) * nodeHalfWidth ))"
equation "d168 = abs(( 0 ) * ( ( ( 1 ) * jointNodeQ * sqrt(2) - bodyWidth / 2 * cos(90 deg) + ( ( -1 ) * nodeHalfWidth ) * sin(90 deg) ) + ( 0.5 ) * ( ( 1 ) * endNodeX - ( ( 1 ) * jointNodeQ * sqrt(2) - bodyWidth / 2 * cos(90 deg) + ( ( -1 ) * nodeHalfWidth ) * sin(90 deg) ) ) ) + ( -1 ) * ( ( -1 ) * nodeHalfWidth ))"
equation "d169 = abs(( 1 ) * ( ( ( 1 ) * jointNodeQ * sqrt(2) - bodyWidth / 2 * cos(90 deg) + ( ( 1 ) * nodeHalfWidth ) * sin(90 deg) ) + ( 1 ) * ( ( 1 ) * endNodeX - ( ( 1 ) * jointNodeQ * sqrt(2) - bodyWidth / 2 * cos(90 deg) + ( ( 1 ) * nodeHalfWidth ) * sin(90 deg) ) ) ) + ( 0 ) * ( ( 1 ) * nodeHalfWidth ))"
equation "d170 = abs(( 0 ) * ( ( ( 1 ) * jointNodeQ * sqrt(2) - bodyWidth / 2 * cos(90 deg) + ( ( 1 ) * nodeHalfWidth ) * sin(90 deg) ) + ( 1 ) * ( ( 1 ) * endNodeX - ( ( 1 ) * jointNodeQ * sqrt(2) - bodyWidth / 2 * cos(90 deg) + ( ( 1 ) * nodeHalfWidth ) * sin(90 deg) ) ) ) + ( -1 ) * ( ( 1 ) * nodeHalfWidth ))"
equation "d171 = memberWidth / 2"
equation "d172 = -( wall + 0.2 mm )"
equation "d174 = abs(( 1 ) * ( ( ( 1 ) * jointNodeQ * sqrt(2) - bodyWidth / 2 * cos(90 deg) + ( ( -1 ) * nodeHalfWidth ) * sin(90 deg) ) + ( 0.5 ) * ( ( 1 ) * endNodeX - ( ( 1 ) * jointNodeQ * sqrt(2) - bodyWidth / 2 * cos(90 deg) + ( ( -1 ) * nodeHalfWidth ) * sin(90 deg) ) ) ) + ( 0 ) * ( ( -1 ) * nodeHalfWidth ))"
equation "d175 = abs(( 0 ) * ( ( ( 1 ) * jointNodeQ * sqrt(2) - bodyWidth / 2 * cos(90 deg) + ( ( -1 ) * nodeHalfWidth ) * sin(90 deg) ) + ( 0.5 ) * ( ( 1 ) * endNodeX - ( ( 1 ) * jointNodeQ * sqrt(2) - bodyWidth / 2 * cos(90 deg) + ( ( -1 ) * nodeHalfWidth ) * sin(90 deg) ) ) ) + ( -1 ) * ( ( -1 ) * nodeHalfWidth ))"
equation "d176 = abs(( 1 ) * ( ( ( 1 ) * jointNodeQ * sqrt(2) - bodyWidth / 2 * cos(90 deg) + ( ( 1 ) * nodeHalfWidth ) * sin(90 deg) ) + ( 1 ) * ( ( 1 ) * endNodeX - ( ( 1 ) * jointNodeQ * sqrt(2) - bodyWidth / 2 * cos(90 deg) + ( ( 1 ) * nodeHalfWidth ) * sin(90 deg) ) ) ) + ( 0 ) * ( ( 1 ) * nodeHalfWidth ))"
equation "d177 = abs(( 0 ) * ( ( ( 1 ) * jointNodeQ * sqrt(2) - bodyWidth / 2 * cos(90 deg) + ( ( 1 ) * nodeHalfWidth ) * sin(90 deg) ) + ( 1 ) * ( ( 1 ) * endNodeX - ( ( 1 ) * jointNodeQ * sqrt(2) - bodyWidth / 2 * cos(90 deg) + ( ( 1 ) * nodeHalfWidth ) * sin(90 deg) ) ) ) + ( -1 ) * ( ( 1 ) * nodeHalfWidth ))"
equation "d178 = abs(( 1 ) * ( ( ( 1 ) * jointNodeQ * sqrt(2) - bodyWidth / 2 * cos(90 deg) + ( ( -1 ) * nodeHalfWidth ) * sin(90 deg) ) + ( 1 ) * ( ( 1 ) * endNodeX - ( ( 1 ) * jointNodeQ * sqrt(2) - bodyWidth / 2 * cos(90 deg) + ( ( -1 ) * nodeHalfWidth ) * sin(90 deg) ) ) ) + ( 0 ) * ( ( -1 ) * nodeHalfWidth ))"
equation "d179 = abs(( 0 ) * ( ( ( 1 ) * jointNodeQ * sqrt(2) - bodyWidth / 2 * cos(90 deg) + ( ( -1 ) * nodeHalfWidth ) * sin(90 deg) ) + ( 1 ) * ( ( 1 ) * endNodeX - ( ( 1 ) * jointNodeQ * sqrt(2) - bodyWidth / 2 * cos(90 deg) + ( ( -1 ) * nodeHalfWidth ) * sin(90 deg) ) ) ) + ( -1 ) * ( ( -1 ) * nodeHalfWidth ))"
equation "d180 = -memberWidth / 2"
equation "d181 = -( wall + 0.2 mm )"
equation "d184 = apertureRadius"
equation "d187 = bodyWidth / 2"
equation "d189 = abs(( 1 ) * ( ( ( 1 ) * jointNodeQ * sqrt(2) - bodyWidth / 2 * cos(135 deg) + ( ( -1 ) * nodeHalfWidth ) * sin(135 deg) ) + ( 0 ) * ( ( 1 ) * endNodeX - ( ( 1 ) * jointNodeQ * sqrt(2) - bodyWidth / 2 * cos(135 deg) + ( ( -1 ) * nodeHalfWidth ) * sin(135 deg) ) ) ) + ( 0 ) * ( ( -1 ) * nodeHalfWidth ))"
equation "d190 = abs(( 0 ) * ( ( ( 1 ) * jointNodeQ * sqrt(2) - bodyWidth / 2 * cos(135 deg) + ( ( -1 ) * nodeHalfWidth ) * sin(135 deg) ) + ( 0 ) * ( ( 1 ) * endNodeX - ( ( 1 ) * jointNodeQ * sqrt(2) - bodyWidth / 2 * cos(135 deg) + ( ( -1 ) * nodeHalfWidth ) * sin(135 deg) ) ) ) + ( -1 ) * ( ( -1 ) * nodeHalfWidth ))"
equation "d191 = abs(( 1 ) * ( ( ( 1 ) * jointNodeQ * sqrt(2) - bodyWidth / 2 * cos(135 deg) + ( ( 1 ) * nodeHalfWidth ) * sin(135 deg) ) + ( 0 ) * ( ( 1 ) * endNodeX - ( ( 1 ) * jointNodeQ * sqrt(2) - bodyWidth / 2 * cos(135 deg) + ( ( 1 ) * nodeHalfWidth ) * sin(135 deg) ) ) ) + ( 0 ) * ( ( 1 ) * nodeHalfWidth ))"
equation "d192 = abs(( 0 ) * ( ( ( 1 ) * jointNodeQ * sqrt(2) - bodyWidth / 2 * cos(135 deg) + ( ( 1 ) * nodeHalfWidth ) * sin(135 deg) ) + ( 0 ) * ( ( 1 ) * endNodeX - ( ( 1 ) * jointNodeQ * sqrt(2) - bodyWidth / 2 * cos(135 deg) + ( ( 1 ) * nodeHalfWidth ) * sin(135 deg) ) ) ) + ( -1 ) * ( ( 1 ) * nodeHalfWidth ))"
equation "d193 = abs(( 1 ) * ( ( ( 1 ) * jointNodeQ * sqrt(2) - bodyWidth / 2 * cos(135 deg) + ( ( -1 ) * nodeHalfWidth ) * sin(135 deg) ) + ( 1 ) * ( ( 1 ) * endNodeX - ( ( 1 ) * jointNodeQ * sqrt(2) - bodyWidth / 2 * cos(135 deg) + ( ( -1 ) * nodeHalfWidth ) * sin(135 deg) ) ) ) + ( 0 ) * ( ( -1 ) * nodeHalfWidth ))"
equation "d194 = abs(( 0 ) * ( ( ( 1 ) * jointNodeQ * sqrt(2) - bodyWidth / 2 * cos(135 deg) + ( ( -1 ) * nodeHalfWidth ) * sin(135 deg) ) + ( 1 ) * ( ( 1 ) * endNodeX - ( ( 1 ) * jointNodeQ * sqrt(2) - bodyWidth / 2 * cos(135 deg) + ( ( -1 ) * nodeHalfWidth ) * sin(135 deg) ) ) ) + ( -1 ) * ( ( -1 ) * nodeHalfWidth ))"
equation "d195 = -memberWidth / 2"